Autodesk Fusion 360 part; units mm, degrees
(part 3 of 5)
sketch "Sketch4" plane through (0, 0, 10) normal (0, 0, 1) x (-1, 0, 0)
  arc A0 (-19.4622, 2.96) -> (-19.5078, 2.643) centre (0, 0) ccw
  arc A1 (-20.5849, 1.781) -> (-19.5078, 2.643) centre (-20.4987, 2.7773) ccw
  line L0 (-20.5849, 1.781) -> (-20.5963, 1.782)
  spline S0 degree 5 poles (-20.5963, 1.782) (-20.606, 1.7828) (-20.6255, 1.7842) (-20.6547, 1.7856) (-20.6937, 1.7861) (-20.7426, 1.7846) (-20.7915, 1.7818) (-20.8404, 1.7781) (-20.8894, 1.7739) (-20.9384, 1.7693) (-20.9874, 1.7645) (-21.0364, 1.7592) (-21.0854, 1.7533) (-21.1344, 1.7468) (-21.1835, 1.7395) (-21.2325, 1.7317) (-21.2815, 1.7232) (-21.3306, 1.7143) (-21.3796, 1.705) (-21.4286, 1.6954) (-21.4776, 1.6853) (-21.5266, 1.6749) (-21.5756, 1.6641) (-21.6246, 1.6528) (-21.6736, 1.6411) (-21.7225, 1.629) (-21.7714, 1.6165) (-21.8204, 1.6036) (-21.8693, 1.5904) (-21.9182, 1.5768) (-21.967, 1.5629) (-22.0159, 1.5487) (-22.0647, 1.5341) (-22.1135, 1.5191) (-22.1622, 1.5038) (-22.211, 1.4882) (-22.2597, 1.4723) (-22.3084, 1.456) (-22.3571, 1.4394) (-22.4057, 1.4225) (-22.4543, 1.4053) (-22.5029, 1.3878) (-22.5514, 1.37) (-22.6, 1.3519) (-22.6484, 1.3335) (-22.6969, 1.3148) (-22.7453, 1.2958) (-22.7937, 1.2765) (-22.842, 1.2569) (-22.8903, 1.237) (-22.9386, 1.2169) (-22.9868, 1.1964) (-23.035, 1.1757) (-23.0832, 1.1548) (-23.1313, 1.1335) (-23.1794, 1.112) (-23.2274, 1.0902) (-23.2754, 1.0681) (-23.3233, 1.0457) (-23.3712, 1.0231) (-23.4191, 1.0003) (-23.4669, 0.9772) (-23.5146, 0.9538) (-23.5624, 0.9301) (-23.61, 0.9062) (-23.6577, 0.8821) (-23.7052, 0.8577) (-23.7528, 0.833) (-23.8002, 0.8081) (-23.8477, 0.7829) (-23.895, 0.7575) (-23.9329, 0.737) (-23.9613, 0.7215) (-23.9802, 0.7111) (-23.9896, 0.7059) knots 0 0 0 0 0 0 0.01428571 0.02857143 0.04285714 0.05714286 0.07142857 0.08571429 0.1 0.11428571 0.12857143 0.14285714 0.15714286 0.17142857 0.18571429 0.2 0.21428571 0.22857143 0.24285714 0.25714286 0.27142857 0.28571429 0.3 0.31428571 0.32857143 0.34285714 0.35714286 0.37142857 0.38571429 0.4 0.41428571 0.42857143 0.44285714 0.45714286 0.47142857 0.48571429 0.5 0.51428571 0.52857143 0.54285714 0.55714286 0.57142857 0.58571429 0.6 0.61428571 0.62857143 0.64285714 0.65714286 0.67142857 0.68571429 0.7 0.71428571 0.72857143 0.74285714 0.75714286 0.77142857 0.78571429 0.8 0.81428571 0.82857143 0.84285714 0.85714286 0.87142857 0.88571429 0.9 0.91428571 0.92857143 0.94285714 0.95714286 0.97142857 0.98571429 1 1 1 1 1 1
  arc A2 (-23.9896, 0.7059) -> (-23.9896, -0.7059) centre (0, 0) ccw
  spline S1 degree 5 poles (-23.9896, -0.7059) (-23.9802, -0.7111) (-23.9613, -0.7215) (-23.9329, -0.737) (-23.895, -0.7575) (-23.8477, -0.7829) (-23.8002, -0.8081) (-23.7528, -0.833) (-23.7052, -0.8577) (-23.6577, -0.8821) (-23.61, -0.9062) (-23.5624, -0.9301) (-23.5146, -0.9538) (-23.4669, -0.9772) (-23.4191, -1.0003) (-23.3712, -1.0231) (-23.3233, -1.0457) (-23.2754, -1.0681) (-23.2274, -1.0902) (-23.1794, -1.112) (-23.1313, -1.1335) (-23.0832, -1.1548) (-23.035, -1.1757) (-22.9868, -1.1964) (-22.9386, -1.2169) (-22.8903, -1.237) (-22.842, -1.2569) (-22.7937, -1.2765) (-22.7453, -1.2958) (-22.6969, -1.3148) (-22.6484, -1.3335) (-22.6, -1.3519) (-22.5514, -1.37) (-22.5029, -1.3878) (-22.4543, -1.4053) (-22.4057, -1.4225) (-22.3571, -1.4394) (-22.3084, -1.456) (-22.2597, -1.4723) (-22.211, -1.4882) (-22.1622, -1.5038) (-22.1135, -1.5191) (-22.0647, -1.5341) (-22.0159, -1.5487) (-21.967, -1.5629) (-21.9182, -1.5768) (-21.8693, -1.5904) (-21.8204, -1.6036) (-21.7714, -1.6165) (-21.7225, -1.629) (-21.6736, -1.6411) (-21.6246, -1.6528) (-21.5756, -1.6641) (-21.5266, -1.6749) (-21.4776, -1.6853) (-21.4286, -1.6954) (-21.3796, -1.705) (-21.3306, -1.7143) (-21.2815, -1.7232) (-21.2325, -1.7317) (-21.1835, -1.7395) (-21.1344, -1.7468) (-21.0854, -1.7533) (-21.0364, -1.7592) (-20.9874, -1.7645) (-20.9384, -1.7693) (-20.8894, -1.7739) (-20.8404, -1.7781) (-20.7915, -1.7818) (-20.7426, -1.7846) (-20.6937, -1.7861) (-20.6547, -1.7856) (-20.6255, -1.7842) (-20.606, -1.7828) (-20.5963, -1.782) knots -1 -1 -1 -1 -1 -1 -0.98571429 -0.97142857 -0.95714286 -0.94285714 -0.92857143 -0.91428571 -0.9 -0.88571429 -0.87142857 -0.85714286 -0.84285714 -0.82857143 -0.81428571 -0.8 -0.78571429 -0.77142857 -0.75714286 -0.74285714 -0.72857143 -0.71428571 -0.7 -0.68571429 -0.67142857 -0.65714286 -0.64285714 -0.62857143 -0.61428571 -0.6 -0.58571429 -0.57142857 -0.55714286 -0.54285714 -0.52857143 -0.51428571 -0.5 -0.48571429 -0.47142857 -0.45714286 -0.44285714 -0.42857143 -0.41428571 -0.4 -0.38571429 -0.37142857 -0.35714286 -0.34285714 -0.32857143 -0.31428571 -0.3 -0.28571429 -0.27142857 -0.25714286 -0.24285714 -0.22857143 -0.21428571 -0.2 -0.18571429 -0.17142857 -0.15714286 -0.14285714 -0.12857143 -0.11428571 -0.1 -0.08571429 -0.07142857 -0.05714286 -0.04285714 -0.02857143 -0.01428571 0 0 0 0 0 0
  line L1 (-20.5963, -1.782) -> (-20.5849, -1.781)
  arc A3 (-19.5078, -2.643) -> (-20.5849, -1.781) centre (-20.4987, -2.7773) ccw
  arc A4 (-19.5078, -2.643) -> (-19.4622, -2.96) centre (0, 0) ccw
  arc A5 (-20.2528, -4.0906) -> (-19.4622, -2.96) centre (-20.4508, -3.1104) ccw
  line L2 (-20.2528, -4.0906) -> (-20.264, -4.0929)
  spline S2 degree 5 poles (-20.264, -4.0929) (-20.2736, -4.0948) (-20.2927, -4.0989) (-20.3211, -4.1058) (-20.3587, -4.1164) (-20.4052, -4.1315) (-20.4513, -4.148) (-20.4972, -4.1654) (-20.543, -4.1832) (-20.5887, -4.2013) (-20.6344, -4.2198) (-20.6799, -4.2387) (-20.7253, -4.2581) (-20.7705, -4.2782) (-20.8155, -4.299) (-20.8603, -4.3204) (-20.905, -4.3423) (-20.9495, -4.3646) (-20.9939, -4.3874) (-21.0382, -4.4104) (-21.0824, -4.4339) (-21.1265, -4.4577) (-21.1705, -4.4819) (-21.2143, -4.5065) (-21.258, -4.5315) (-21.3015, -4.5569) (-21.345, -4.5827) (-21.3883, -4.6089) (-21.4315, -4.6353) (-21.4746, -4.6621) (-21.5175, -4.6892) (-21.5604, -4.7167) (-21.6031, -4.7444) (-21.6457, -4.7725) (-21.6882, -4.8009) (-21.7306, -4.8296) (-21.7728, -4.8586) (-21.815, -4.888) (-21.857, -4.9176) (-21.8989, -4.9475) (-21.9407, -4.9777) (-21.9824, -5.0082) (-22.0239, -5.039) (-22.0654, -5.07) (-22.1067, -5.1013) (-22.1479, -5.1329) (-22.189, -5.1648) (-22.23, -5.1969) (-22.2709, -5.2294) (-22.3116, -5.262) (-22.3523, -5.295) (-22.3928, -5.3282) (-22.4332, -5.3616) (-22.4735, -5.3953) (-22.5136, -5.4293) (-22.5537, -5.4635) (-22.5936, -5.4979) (-22.6335, -5.5326) (-22.6732, -5.5675) (-22.7128, -5.6027) (-22.7522, -5.6382) (-22.7916, -5.6738) (-22.8308, -5.7097) (-22.87, -5.7458) (-22.909, -5.7822) (-22.9479, -5.8188) (-22.9866, -5.8556) (-23.0253, -5.8927) (-23.0638, -5.9299) (-23.1022, -5.9674) (-23.1405, -6.0052) (-23.1711, -6.0355) (-23.1939, -6.0584) (-23.2091, -6.0737) (-23.2167, -6.0813) knots 0 0 0 0 0 0 0.01428571 0.02857143 0.04285714 0.05714286 0.07142857 0.08571429 0.1 0.11428571 0.12857143 0.14285714 0.15714286 0.17142857 0.18571429 0.2 0.21428571 0.22857143 0.24285714 0.25714286 0.27142857 0.28571429 0.3 0.31428571 0.32857143 0.34285714 0.35714286 0.37142857 0.38571429 0.4 0.41428571 0.42857143 0.44285714 0.45714286 0.47142857 0.48571429 0.5 0.51428571 0.52857143 0.54285714 0.55714286 0.57142857 0.58571429 0.6 0.61428571 0.62857143 0.64285714 0.65714286 0.67142857 0.68571429 0.7 0.71428571 0.72857143 0.74285714 0.75714286 0.77142857 0.78571429 0.8 0.81428571 0.82857143 0.84285714 0.85714286 0.87142857 0.88571429 0.9 0.91428571 0.92857143 0.94285714 0.95714286 0.97142857 0.98571429 1 1 1 1 1 1
  arc A6 (-23.2167, -6.0813) -> (-22.819, -7.436) centre (0, 0) ccw
  spline S3 degree 5 poles (-22.819, -7.436) (-22.8085, -7.4383) (-22.7874, -7.4429) (-22.7558, -7.4498) (-22.7137, -7.4589) (-22.6611, -7.4699) (-22.6085, -7.4807) (-22.5559, -7.4912) (-22.5034, -7.5015) (-22.4508, -7.5115) (-22.3984, -7.5212) (-22.3459, -7.5307) (-22.2934, -7.54) (-22.241, -7.549) (-22.1886, -7.5577) (-22.1363, -7.5661) (-22.0839, -7.5743) (-22.0316, -7.5823) (-21.9794, -7.5899) (-21.9272, -7.5973) (-21.875, -7.6044) (-21.8228, -7.6113) (-21.7707, -7.6178) (-21.7186, -7.6241) (-21.6666, -7.6301) (-21.6146, -7.6359) (-21.5627, -7.6413) (-21.5108, -7.6465) (-21.4589, -7.6514) (-21.4071, -7.656) (-21.3553, -7.6603) (-21.3036, -7.6643) (-21.252, -7.668) (-21.2004, -7.6714) (-21.1488, -7.6745) (-21.0973, -7.6773) (-21.0459, -7.6798) (-20.9946, -7.682) (-20.9433, -7.6839) (-20.892, -7.6855) (-20.8408, -7.6867) (-20.7897, -7.6877) (-20.7387, -7.6883) (-20.6878, -7.6885) (-20.6369, -7.6884) (-20.5861, -7.688) (-20.5353, -7.6873) (-20.4847, -7.6862) (-20.4341, -7.6847) (-20.3837, -7.6829) (-20.3333, -7.6808) (-20.283, -7.6782) (-20.2328, -7.6752) (-20.1828, -7.6718) (-20.1328, -7.668) (-20.083, -7.6638) (-20.0332, -7.6593) (-19.9835, -7.6544) (-19.934, -7.6491) (-19.8846, -7.6434) (-19.8353, -7.6371) (-19.7862, -7.6303) (-19.7373, -7.6228) (-19.6886, -7.6146) (-19.6401, -7.6058) (-19.5917, -7.5967) (-19.5435, -7.5872) (-19.4953, -7.5775) (-19.4473, -7.5673) (-19.3996, -7.5562) (-19.3523, -7.5438) (-19.315, -7.5324) (-19.2873, -7.5228) (-19.2691, -7.516) (-19.26, -7.5124) knots -1 -1 -1 -1 -1 -1 -0.98571429 -0.97142857 -0.95714286 -0.94285714 -0.92857143 -0.91428571 -0.9 -0.88571429 -0.87142857 -0.85714286 -0.84285714 -0.82857143 -0.81428571 -0.8 -0.78571429 -0.77142857 -0.75714286 -0.74285714 -0.72857143 -0.71428571 -0.7 -0.68571429 -0.67142857 -0.65714286 -0.64285714 -0.62857143 -0.61428571 -0.6 -0.58571429 -0.57142857 -0.55714286 -0.54285714 -0.52857143 -0.51428571 -0.5 -0.48571429 -0.47142857 -0.45714286 -0.44285714 -0.42857143 -0.41428571 -0.4 -0.38571429 -0.37142857 -0.35714286 -0.34285714 -0.32857143 -0.31428571 -0.3 -0.28571429 -0.27142857 -0.25714286 -0.24285714 -0.22857143 -0.21428571 -0.2 -0.18571429 -0.17142857 -0.15714286 -0.14285714 -0.12857143 -0.11428571 -0.1 -0.08571429 -0.07142857 -0.05714286 -0.04285714 -0.02857143 -0.01428571 0 0 0 0 0 0
  line L3 (-19.26, -7.5124) -> (-19.2493, -7.5083)
  arc A7 (-17.9729, -8.0319) -> (-19.2493, -7.5083) centre (-18.8859, -8.4399) ccw
  arc A8 (-17.9729, -8.0319) -> (-17.8399, -8.3233) centre (0, 0) ccw
  arc A9 (-18.28, -9.6308) -> (-17.8399, -8.3233) centre (-18.7461, -8.7461) ccw
  line L4 (-18.28, -9.6308) -> (-18.2901, -9.6361)
  spline S4 degree 5 poles (-18.2901, -9.6361) (-18.2988, -9.6407) (-18.3159, -9.65) (-18.3413, -9.6646) (-18.3743, -9.6853) (-18.4146, -9.713) (-18.4542, -9.7418) (-18.4934, -9.7714) (-18.5323, -9.8014) (-18.5711, -9.8317) (-18.6097, -9.8622) (-18.648, -9.8932) (-18.6861, -9.9246) (-18.7238, -9.9567) (-18.7611, -9.9893) (-18.7981, -10.0224) (-18.8348, -10.056) (-18.8712, -10.09) (-18.9075, -10.1243) (-18.9435, -10.1589) (-18.9793, -10.1939) (-19.0149, -10.2291) (-19.0502, -10.2648) (-19.0853, -10.3007) (-19.1202, -10.337) (-19.1548, -10.3737) (-19.1892, -10.4107) (-19.2234, -10.4479) (-19.2574, -10.4855) (-19.2912, -10.5233) (-19.3248, -10.5615) (-19.3582, -10.5999) (-19.3914, -10.6385) (-19.4243, -10.6775) (-19.4571, -10.7167) (-19.4897, -10.7562) (-19.522, -10.7959) (-19.5542, -10.836) (-19.5862, -10.8762) (-19.618, -10.9167) (-19.6496, -10.9575) (-19.681, -10.9985) (-19.7122, -11.0397) (-19.7432, -11.0812) (-19.774, -11.1229) (-19.8047, -11.1648) (-19.8351, -11.207) (-19.8654, -11.2494) (-19.8955, -11.292) (-19.9254, -11.3348) (-19.9551, -11.3778) (-19.9846, -11.4211) (-20.0139, -11.4646) (-20.0431, -11.5083) (-20.0721, -11.5522) (-20.1009, -11.5963) (-20.1295, -11.6406) (-20.1579, -11.6851) (-20.1862, -11.7298) (-20.2143, -11.7747) (-20.2422, -11.8198) (-20.2699, -11.8651) (-20.2974, -11.9106) (-20.3248, -11.9563) (-20.352, -12.0022) (-20.379, -12.0483) (-20.4058, -12.0945) (-20.4324, -12.1409) (-20.4589, -12.1876) (-20.4852, -12.2344) (-20.5113, -12.2814) (-20.5321, -12.3191) (-20.5476, -12.3475) (-20.5579, -12.3664) (-20.563, -12.3759) knots 0 0 0 0 0 0 0.01428571 0.02857143 0.04285714 0.05714286 0.07142857 0.08571429 0.1 0.11428571 0.12857143 0.14285714 0.15714286 0.17142857 0.18571429 0.2 0.21428571 0.22857143 0.24285714 0.25714286 0.27142857 0.28571429 0.3 0.31428571 0.32857143 0.34285714 0.35714286 0.37142857 0.38571429 0.4 0.41428571 0.42857143 0.44285714 0.45714286 0.47142857 0.48571429 0.5 0.51428571 0.52857143 0.54285714 0.55714286 0.57142857 0.58571429 0.6 0.61428571 0.62857143 0.64285714 0.65714286 0.67142857 0.68571429 0.7 0.71428571 0.72857143 0.74285714 0.75714286 0.77142857 0.78571429 0.8 0.81428571 0.82857143 0.84285714 0.85714286 0.87142857 0.88571429 0.9 0.91428571 0.92857143 0.94285714 0.95714286 0.97142857 0.98571429 1 1 1 1 1 1
  arc A10 (-20.563, -12.3759) -> (-19.7997, -13.5636) centre (0, 0) ccw
  spline S5 degree 5 poles (-19.7997, -13.5636) (-19.7889, -13.5629) (-19.7674, -13.5614) (-19.7352, -13.5591) (-19.6922, -13.5559) (-19.6386, -13.5517) (-19.5851, -13.5472) (-19.5317, -13.5425) (-19.4784, -13.5375) (-19.4252, -13.5323) (-19.3721, -13.5269) (-19.3191, -13.5212) (-19.2661, -13.5153) (-19.2133, -13.5092) (-19.1606, -13.5028) (-19.108, -13.4962) (-19.0554, -13.4893) (-19.003, -13.4821) (-18.9507, -13.4748) (-18.8985, -13.4671) (-18.8465, -13.4593) (-18.7945, -13.4511) (-18.7426, -13.4428) (-18.6909, -13.4341) (-18.6393, -13.4252) (-18.5878, -13.4161) (-18.5364, -13.4067) (-18.4851, -13.397) (-18.434, -13.3871) (-18.383, -13.3769) (-18.3321, -13.3665) (-18.2814, -13.3558) (-18.2308, -13.3448) (-18.1803, -13.3335) (-18.13, -13.322) (-18.0798, -13.3102) (-18.0298, -13.2981) (-17.9798, -13.2857) (-17.9301, -13.2731) (-17.8805, -13.2601) (-17.831, -13.2469) (-17.7817, -13.2334) (-17.7326, -13.2196) (-17.6836, -13.2055) (-17.6349, -13.1911) (-17.5862, -13.1764) (-17.5378, -13.1613) (-17.4895, -13.146) (-17.4414, -13.1304) (-17.3934, -13.1145) (-17.3457, -13.0982) (-17.2982, -13.0815) (-17.2509, -13.0646) (-17.2038, -13.0472) (-17.157, -13.0295) (-17.1103, -13.0114) (-17.0638, -12.993) (-17.0176, -12.9744) (-16.9715, -12.9553) (-16.9257, -12.9359) (-16.8802, -12.916) (-16.835, -12.8956) (-16.7902, -12.8746) (-16.7458, -12.8531) (-16.7017, -12.831) (-16.6579, -12.8086) (-16.6142, -12.7859) (-16.5708, -12.763) (-16.5276, -12.7397) (-16.4849, -12.7156) (-16.4431, -12.6904) (-16.4105, -12.669) (-16.3866, -12.652) (-16.371, -12.6403) (-16.3633, -12.6343) knots -1 -1 -1 -1 -1 -1 -0.98571429 -0.97142857 -0.95714286 -0.94285714 -0.92857143 -0.91428571 -0.9 -0.88571429 -0.87142857 -0.85714286 -0.84285714 -0.82857143 -0.81428571 -0.8 -0.78571429 -0.77142857 -0.75714286 -0.74285714 -0.72857143 -0.71428571 -0.7 -0.68571429 -0.67142857 -0.65714286 -0.64285714 -0.62857143 -0.61428571 -0.6 -0.58571429 -0.57142857 -0.55714286 -0.54285714 -0.52857143 -0.51428571 -0.5 -0.48571429 -0.47142857 -0.45714286 -0.44285714 -0.42857143 -0.41428571 -0.4 -0.38571429 -0.37142857 -0.35714286 -0.34285714 -0.32857143 -0.31428571 -0.3 -0.28571429 -0.27142857 -0.25714286 -0.24285714 -0.22857143 -0.21428571 -0.2 -0.18571429 -0.17142857 -0.15714286 -0.14285714 -0.12857143 -0.11428571 -0.1 -0.08571429 -0.07142857 -0.05714286 -0.04285714 -0.02857143 -0.01428571 0 0 0 0 0 0
  line L5 (-16.3633, -12.6343) -> (-16.3543, -12.6273)
  arc A11 (-14.9821, -12.7701) -> (-16.3543, -12.6273) centre (-15.7431, -13.4188) ccw
  arc A12 (-14.9821, -12.7701) -> (-14.7723, -13.0122) centre (0, 0) ccw
  arc A13 (-14.8262, -14.3907) -> (-14.7723, -13.0122) centre (-15.5227, -13.6732) ccw
  line L6 (-14.8262, -14.3907) -> (-14.8344, -14.3987)
  spline S6 degree 5 poles (-14.8344, -14.3987) (-14.8414, -14.4055) (-14.8553, -14.4193) (-14.8755, -14.4405) (-14.9013, -14.4697) (-14.9322, -14.5075) (-14.9621, -14.5463) (-14.9914, -14.5858) (-15.0202, -14.6255) (-15.0489, -14.6655) (-15.0773, -14.7057) (-15.1054, -14.7462) (-15.1331, -14.7871) (-15.1602, -14.8284) (-15.1869, -14.8702) (-15.213, -14.9125) (-15.2388, -14.955) (-15.2641, -14.9979) (-15.2892, -15.041) (-15.314, -15.0844) (-15.3385, -15.128) (-15.3628, -15.1719) (-15.3866, -15.216) (-15.4102, -15.2604) (-15.4334, -15.3051) (-15.4563, -15.35) (-15.4789, -15.3952) (-15.5012, -15.4406) (-15.5233, -15.4862) (-15.545, -15.532) (-15.5665, -15.5781) (-15.5877, -15.6243) (-15.6087, -15.6708) (-15.6293, -15.7174) (-15.6497, -15.7643) (-15.6698, -15.8114) (-15.6897, -15.8586) (-15.7093, -15.9061) (-15.7286, -15.9537) (-15.7477, -16.0015) (-15.7665, -16.0495) (-15.7851, -16.0977) (-15.8034, -16.1461) (-15.8215, -16.1946) (-15.8394, -16.2433) (-15.8569, -16.2922) (-15.8743, -16.3412) (-15.8914, -16.3904) (-15.9082, -16.4398) (-15.9249, -16.4893) (-15.9412, -16.5389) (-15.9574, -16.5888) (-15.9733, -16.6388) (-15.989, -16.6889) (-16.0044, -16.7392) (-16.0196, -16.7896) (-16.0346, -16.8402) (-16.0493, -16.8909) (-16.0638, -16.9418) (-16.0781, -16.9928) (-16.0922, -17.0439) (-16.106, -17.0952) (-16.1196, -17.1466) (-16.133, -17.1981) (-16.1462, -17.2498) (-16.1591, -17.3016) (-16.1718, -17.3536) (-16.1843, -17.4056) (-16.1966, -17.4578) (-16.2086, -17.5101) (-16.2204, -17.5626) (-16.2297, -17.6046) (-16.2366, -17.6362) (-16.2411, -17.6573) (-16.2434, -17.6679) knots 0 0 0 0 0 0 0.01428571 0.02857143 0.04285714 0.05714286 0.07142857 0.08571429 0.1 0.11428571 0.12857143 0.14285714 0.15714286 0.17142857 0.18571429 0.2 0.21428571 0.22857143 0.24285714 0.25714286 0.27142857 0.28571429 0.3 0.31428571 0.32857143 0.34285714 0.35714286 0.37142857 0.38571429 0.4 0.41428571 0.42857143 0.44285714 0.45714286 0.47142857 0.48571429 0.5 0.51428571 0.52857143 0.54285714 0.55714286 0.57142857 0.58571429 0.6 0.61428571 0.62857143 0.64285714 0.65714286 0.67142857 0.68571429 0.7 0.71428571 0.72857143 0.74285714 0.75714286 0.77142857 0.78571429 0.8 0.81428571 0.82857143 0.84285714 0.85714286 0.87142857 0.88571429 0.9 0.91428571 0.92857143 0.94285714 0.95714286 0.97142857 0.98571429 1 1 1 1 1 1
  arc A14 (-16.2434, -17.6679) -> (-15.1764, -18.5924) centre (0, 0) ccw
  spline S7 degree 5 poles (-15.1764, -18.5924) (-15.1662, -18.5887) (-15.146, -18.5812) (-15.1157, -18.5699) (-15.0754, -18.5547) (-15.0252, -18.5356) (-14.9751, -18.5162) (-14.9252, -18.4966) (-14.8754, -18.4769) (-14.8258, -18.4569) (-14.7764, -18.4367) (-14.7271, -18.4163) (-14.678, -18.3958) (-14.6291, -18.375) (-14.5803, -18.354) (-14.5316, -18.3328) (-14.4832, -18.3114) (-14.4349, -18.2898) (-14.3868, -18.268) (-14.3389, -18.246) (-14.2911, -18.2237) (-14.2436, -18.2013) (-14.1962, -18.1787) (-14.149, -18.1558) (-14.1019, -18.1327) (-14.0551, -18.1094) (-14.0084, -18.0859) (-13.962, -18.0622) (-13.9157, -18.0383) (-13.8697, -18.0142) (-13.8238, -17.9898) (-13.7781, -17.9652) (-13.7327, -17.9404) (-13.6874, -17.9154) (-13.6424, -17.8901) (-13.5975, -17.8647) (-13.5529, -17.839) (-13.5085, -17.8131) (-13.4643, -17.7869) (-13.4204, -17.7605) (-13.3767, -17.7339) (-13.3332, -17.7071) (-13.2899, -17.68) (-13.2469, -17.6526) (-13.2042, -17.6251) (-13.1617, -17.5972) (-13.1194, -17.5692) (-13.0774, -17.5409) (-13.0356, -17.5123) (-12.9941, -17.4835) (-12.9529, -17.4545) (-12.912, -17.4251) (-12.8714, -17.3955) (-12.8311, -17.3656) (-12.7912, -17.3354) (-12.7515, -17.3049) (-12.7121, -17.2742) (-12.6729, -17.2432) (-12.6341, -17.212) (-12.5956, -17.1804) (-12.5576, -17.1485) (-12.52, -17.1162) (-12.4829, -17.0835) (-12.4464, -17.0503) (-12.4103, -17.0167) (-12.3745, -16.9828) (-12.339, -16.9488) (-12.3038, -16.9145) (-12.2689, -16.88) (-12.2348, -16.8449) (-12.2017, -16.8089) (-12.1765, -16.7791) (-12.1584, -16.7561) (-12.1467, -16.7405) (-12.141, -16.7326) knots -1 -1 -1 -1 -1 -1 -0.98571429 -0.97142857 -0.95714286 -0.94285714 -0.92857143 -0.91428571 -0.9 -0.88571429 -0.87142857 -0.85714286 -0.84285714 -0.82857143 -0.81428571 -0.8 -0.78571429 -0.77142857 -0.75714286 -0.74285714 -0.72857143 -0.71428571 -0.7 -0.68571429 -0.67142857 -0.65714286 -0.64285714 -0.62857143 -0.61428571 -0.6 -0.58571429 -0.57142857 -0.55714286 -0.54285714 -0.52857143 -0.51428571 -0.5 -0.48571429 -0.47142857 -0.45714286 -0.44285714 -0.42857143 -0.41428571 -0.4 -0.38571429 -0.37142857 -0.35714286 -0.34285714 -0.32857143 -0.31428571 -0.3 -0.28571429 -0.27142857 -0.25714286 -0.24285714 -0.22857143 -0.21428571 -0.2 -0.18571429 -0.17142857 -0.15714286 -0.14285714 -0.12857143 -0.11428571 -0.1 -0.08571429 -0.07142857 -0.05714286 -0.04285714 -0.02857143 -0.01428571 0 0 0 0 0 0
  line L7 (-12.141, -16.7326) -> (-12.1343, -16.7233)
  arc A15 (-10.7774, -16.4738) -> (-12.1343, -16.7233) centre (-11.3249, -17.3106) ccw
  arc A16 (-10.7774, -16.4738) -> (-10.508, -16.6469) centre (0, 0) ccw
  arc A17 (-10.1713, -17.9848) -> (-10.508, -16.6469) centre (-11.0418, -17.4926) ccw
  line L8 (-10.1713, -17.9848) -> (-10.1769, -17.9948)
  spline S8 degree 5 poles (-10.1769, -17.9948) (-10.1818, -18.0033) (-10.1912, -18.0204) (-10.2046, -18.0464) (-10.2212, -18.0817) (-10.2401, -18.1268) (-10.2579, -18.1724) (-10.2748, -18.2185) (-10.2913, -18.2648) (-10.3076, -18.3112) (-10.3235, -18.3578) (-10.3391, -18.4046) (-10.3541, -18.4516) (-10.3685, -18.4989) (-10.3823, -18.5465) (-10.3955, -18.5944) (-10.4082, -18.6425) (-10.4204, -18.6908) (-10.4324, -18.7393) (-10.4439, -18.7879) (-10.4552, -18.8366) (-10.466, -18.8855) (-10.4765, -18.9346) (-10.4866, -18.9838) (-10.4963, -19.0332) (-10.5056, -19.0828) (-10.5146, -19.1325) (-10.5232, -19.1823) (-10.5315, -19.2323) (-10.5395, -19.2824) (-10.5471, -19.3326) (-10.5544, -19.383) (-10.5614, -19.4335) (-10.5681, -19.4841) (-10.5745, -19.5348) (-10.5805, -19.5856) (-10.5863, -19.6365) (-10.5917, -19.6876) (-10.5968, -19.7387) (-10.6017, -19.79) (-10.6062, -19.8414) (-10.6105, -19.8928) (-10.6144, -19.9444) (-10.6181, -19.996) (-10.6215, -20.0478) (-10.6246, -20.0996) (-10.6274, -20.1516) (-10.63, -20.2036) (-10.6322, -20.2557) (-10.6342, -20.3079) (-10.636, -20.3602) (-10.6374, -20.4125) (-10.6386, -20.465) (-10.6395, -20.5175) (-10.6401, -20.5701) (-10.6405, -20.6228) (-10.6406, -20.6755) (-10.6405, -20.7283) (-10.6401, -20.7812) (-10.6394, -20.8342) (-10.6385, -20.8872) (-10.6373, -20.9403) (-10.6359, -20.9935) (-10.6342, -21.0467) (-10.6323, -21.1) (-10.6301, -21.1533) (-10.6277, -21.2068) (-10.625, -21.2602) (-10.622, -21.3138) (-10.6189, -21.3673) (-10.6154, -21.421) (-10.6125, -21.464) (-10.6102, -21.4962) (-10.6086, -21.5177) (-10.6078, -21.5285) knots 0 0 0 0 0 0 0.01428571 0.02857143 0.04285714 0.05714286 0.07142857 0.08571429 0.1 0.11428571 0.12857143 0.14285714 0.15714286 0.17142857 0.18571429 0.2 0.21428571 0.22857143 0.24285714 0.25714286 0.27142857 0.28571429 0.3 0.31428571 0.32857143 0.34285714 0.35714286 0.37142857 0.38571429 0.4 0.41428571 0.42857143 0.44285714 0.45714286 0.47142857 0.48571429 0.5 0.51428571 0.52857143 0.54285714 0.55714286 0.57142857 0.58571429 0.6 0.61428571 0.62857143 0.64285714 0.65714286 0.67142857 0.68571429 0.7 0.71428571 0.72857143 0.74285714 0.75714286 0.77142857 0.78571429 0.8 0.81428571 0.82857143 0.84285714 0.85714286 0.87142857 0.88571429 0.9 0.91428571 0.92857143 0.94285714 0.95714286 0.97142857 0.98571429 1 1 1 1 1 1
  arc A18 (-10.6078, -21.5285) -> (-9.3235, -22.115) centre (0, 0) ccw
  spline S9 degree 5 poles (-9.3235, -22.115) (-9.3149, -22.1085) (-9.2976, -22.0957) (-9.2717, -22.0763) (-9.2373, -22.0504) (-9.1945, -22.0178) (-9.1519, -21.9851) (-9.1095, -21.9523) (-9.0674, -21.9193) (-9.0254, -21.8862) (-8.9836, -21.8529) (-8.9421, -21.8195) (-8.9008, -21.7859) (-8.8596, -21.7522) (-8.8187, -21.7183) (-8.7781, -21.6842) (-8.7376, -21.6501) (-8.6974, -21.6157) (-8.6574, -21.5812) (-8.6176, -21.5466) (-8.578, -21.5118) (-8.5387, -21.4769) (-8.4996, -21.4418) (-8.4607, -21.4066) (-8.4221, -21.3712) (-8.3837, -21.3357) (-8.3456, -21.3) (-8.3077, -21.2641) (-8.2701, -21.2281) (-8.2327, -21.192) (-8.1955, -21.1557) (-8.1586, -21.1192) (-8.122, -21.0826) (-8.0856, -21.0459) (-8.0495, -21.009) (-8.0137, -20.9719) (-7.9781, -20.9347) (-7.9428, -20.8973) (-7.9078, -20.8598) (-7.873, -20.8221) (-7.8386, -20.7842) (-7.8044, -20.7462) (-7.7706, -20.708) (-7.737, -20.6697) (-7.7038, -20.6312) (-7.6708, -20.5925) (-7.6382, -20.5537) (-7.6058, -20.5147) (-7.5738, -20.4755) (-7.5421, -20.4362) (-7.5107, -20.3967) (-7.4798, -20.357) (-7.4491, -20.3171) (-7.4189, -20.2771) (-7.3891, -20.2368) (-7.3596, -20.1964) (-7.3304, -20.1559) (-7.3016, -20.1151) (-7.2732, -20.0742) (-7.2451, -20.0331) (-7.2176, -19.9918) (-7.1906, -19.9502) (-7.1643, -19.9083) (-7.1386, -19.8662) (-7.1134, -19.8238) (-7.0887, -19.7812) (-7.0642, -19.7385) (-7.04, -19.6958) (-7.0163, -19.6528) (-6.9934, -19.6095) (-6.9718, -19.5657) (-6.956, -19.53) (-6.9451, -19.5028) (-6.9383, -19.4845) (-6.9351, -19.4753) knots -1 -1 -1 -1 -1 -1 -0.98571429 -0.97142857 -0.95714286 -0.94285714 -0.92857143 -0.91428571 -0.9 -0.88571429 -0.87142857 -0.85714286 -0.84285714 -0.82857143 -0.81428571 -0.8 -0.78571429 -0.77142857 -0.75714286 -0.74285714 -0.72857143 -0.71428571 -0.7 -0.68571429 -0.67142857 -0.65714286 -0.64285714 -0.62857143 -0.61428571 -0.6 -0.58571429 -0.57142857 -0.55714286 -0.54285714 -0.52857143 -0.51428571 -0.5 -0.48571429 -0.47142857 -0.45714286 -0.44285714 -0.42857143 -0.41428571 -0.4 -0.38571429 -0.37142857 -0.35714286 -0.34285714 -0.32857143 -0.31428571 -0.3 -0.28571429 -0.27142857 -0.25714286 -0.24285714 -0.22857143 -0.21428571 -0.2 -0.18571429 -0.17142857 -0.15714286 -0.14285714 -0.12857143 -0.11428571 -0.1 -0.08571429 -0.07142857 -0.05714286 -0.04285714 -0.02857143 -0.01428571 0 0 0 0 0 0
  line L9 (-6.9351, -19.4753) -> (-6.9312, -19.4645)
  arc A19 (-5.6997, -18.8428) -> (-6.9312, -19.4645) centre (-5.9892, -19.8) ccw
  arc A20 (-5.6997, -18.8428) -> (-5.3924, -18.9331) centre (0, 0) ccw
  arc A21 (-4.6924, -20.1219) -> (-5.3924, -18.9331) centre (-5.6663, -19.8948) ccw
  line L10 (-4.6924, -20.1219) -> (-4.695, -20.1331)
  spline S10 degree 5 poles (-4.695, -20.1331) (-4.6972, -20.1426) (-4.7014, -20.1616) (-4.7069, -20.1904) (-4.7129, -20.2289) (-4.7185, -20.2775) (-4.7226, -20.3263) (-4.7259, -20.3753) (-4.7287, -20.4243) (-4.7312, -20.4734) (-4.7334, -20.5226) (-4.7351, -20.5719) (-4.7363, -20.6213) (-4.7367, -20.6707) (-4.7365, -20.7203) (-4.7357, -20.7699) (-4.7344, -20.8197) (-4.7325, -20.8695) (-4.7303, -20.9193) (-4.7277, -20.9692) (-4.7248, -21.0192) (-4.7214, -21.0691) (-4.7177, -21.1192) (-4.7135, -21.1693) (-4.7089, -21.2194) (-4.7038, -21.2696) (-4.6984, -21.3198) (-4.6927, -21.3701) (-4.6865, -21.4203) (-4.6801, -21.4707) (-4.6732, -21.521) (-4.6661, -21.5714) (-4.6586, -21.6218) (-4.6507, -21.6722) (-4.6425, -21.7226) (-4.634, -21.7731) (-4.6252, -21.8236) (-4.616, -21.8741) (-4.6065, -21.9247) (-4.5967, -21.9752) (-4.5866, -22.0258) (-4.5762, -22.0763) (-4.5655, -22.1269) (-4.5545, -22.1775) (-4.5431, -22.2281) (-4.5315, -22.2788) (-4.5196, -22.3294) (-4.5074, -22.38) (-4.4949, -22.4307) (-4.4821, -22.4813) (-4.469, -22.5319) (-4.4556, -22.5826) (-4.442, -22.6332) (-4.4281, -22.6839) (-4.4139, -22.7345) (-4.3994, -22.7852) (-4.3847, -22.8358) (-4.3696, -22.8865) (-4.3544, -22.9371) (-4.3388, -22.9877) (-4.323, -23.0383) (-4.3069, -23.089) (-4.2905, -23.1396) (-4.2739, -23.1902) (-4.2571, -23.2408) (-4.2399, -23.2913) (-4.2225, -23.3419) (-4.2049, -23.3924) (-4.187, -23.443) (-4.1688, -23.4935) (-4.1504, -23.544) (-4.1355, -23.5844) (-4.1242, -23.6147) (-4.1166, -23.6349) (-4.1128, -23.645) knots 0 0 0 0 0 0 0.01428571 0.02857143 0.04285714 0.05714286 0.07142857 0.08571429 0.1 0.11428571 0.12857143 0.14285714 0.15714286 0.17142857 0.18571429 0.2 0.21428571 0.22857143 0.24285714 0.25714286 0.27142857 0.28571429 0.3 0.31428571 0.32857143 0.34285714 0.35714286 0.37142857 0.38571429 0.4 0.41428571 0.42857143 0.44285714 0.45714286 0.47142857 0.48571429 0.5 0.51428571 0.52857143 0.54285714 0.55714286 0.57142857 0.58571429 0.6 0.61428571 0.62857143 0.64285714 0.65714286 0.67142857 0.68571429 0.7 0.71428571 0.72857143 0.74285714 0.75714286 0.77142857 0.78571429 0.8 0.81428571 0.82857143 0.84285714 0.85714286 0.87142857 0.88571429 0.9 0.91428571 0.92857143 0.94285714 0.95714286 0.97142857 0.98571429 1 1 1 1 1 1
  arc A22 (-4.1128, -23.645) -> (-2.7153, -23.8459) centre (0, 0) ccw
  spline S11 degree 5 poles (-2.7153, -23.8459) (-2.7088, -23.8373) (-2.6959, -23.8201) (-2.6765, -23.7942) (-2.6508, -23.7596) (-2.6189, -23.7163) (-2.5873, -23.673) (-2.5558, -23.6295) (-2.5247, -23.586) (-2.4937, -23.5424) (-2.4631, -23.4987) (-2.4326, -23.4549) (-2.4024, -23.411) (-2.3725, -23.3671) (-2.3428, -23.3231) (-2.3133, -23.2789) (-2.2841, -23.2347) (-2.2552, -23.1905) (-2.2265, -23.1461) (-2.1981, -23.1017) (-2.17, -23.0572) (-2.1421, -23.0126) (-2.1145, -22.9679) (-2.0871, -22.9231) (-2.06, -22.8783) (-2.0332, -22.8334) (-2.0067, -22.7884) (-1.9804, -22.7433) (-1.9544, -22.6982) (-1.9287, -22.653) (-1.9033, -22.6077) (-1.8782, -22.5623) (-1.8533, -22.5169) (-1.8288, -22.4714) (-1.8045, -22.4258) (-1.7806, -22.3801) (-1.757, -22.3344) (-1.7336, -22.2886) (-1.7106, -22.2427) (-1.6879, -22.1967) (-1.6655, -22.1507) (-1.6434, -22.1046) (-1.6217, -22.0584) (-1.6003, -22.0122) (-1.5792, -21.9659) (-1.5585, -21.9195) (-1.5381, -21.873) (-1.5181, -21.8265) (-1.4984, -21.7799) (-1.479, -21.7332) (-1.4601, -21.6865) (-1.4415, -21.6397) (-1.4234, -21.5928) (-1.4057, -21.5459) (-1.3884, -21.4989) (-1.3715, -21.4518) (-1.3549, -21.4046) (-1.3388, -21.3574) (-1.323, -21.3102) (-1.3077, -21.2628) (-1.2929, -21.2154) (-1.2787, -21.1679) (-1.2653, -21.1203) (-1.2525, -21.0726) (-1.2403, -21.0249) (-1.2285, -20.9771) (-1.2171, -20.9292) (-1.2059, -20.8813) (-1.1953, -20.8334) (-1.1855, -20.7854) (-1.1771, -20.7373) (-1.172, -20.6986) (-1.1692, -20.6695) (-1.1679, -20.65) (-1.1673, -20.6403) knots -1 -1 -1 -1 -1 -1 -0.98571429 -0.97142857 -0.95714286 -0.94285714 -0.92857143 -0.91428571 -0.9 -0.88571429 -0.87142857 -0.85714286 -0.84285714 -0.82857143 -0.81428571 -0.8 -0.78571429 -0.77142857 -0.75714286 -0.74285714 -0.72857143 -0.71428571 -0.7 -0.68571429 -0.67142857 -0.65714286 -0.64285714 -0.62857143 -0.61428571 -0.6 -0.58571429 -0.57142857 -0.55714286 -0.54285714 -0.52857143 -0.51428571 -0.5 -0.48571429 -0.47142857 -0.45714286 -0.44285714 -0.42857143 -0.41428571 -0.4 -0.38571429 -0.37142857 -0.35714286 -0.34285714 -0.32857143 -0.31428571 -0.3 -0.28571429 -0.27142857 -0.25714286 -0.24285714 -0.22857143 -0.21428571 -0.2 -0.18571429 -0.17142857 -0.15714286 -0.14285714 -0.12857143 -0.11428571 -0.1 -0.08571429 -0.07142857 -0.05714286 -0.04285714 -0.02857143 -0.01428571 0 0 0 0 0 0
  line L11 (-1.1673, -20.6403) -> (-1.1667, -20.6289)
  arc A23 (-0.1601, -19.6853) -> (-1.1667, -20.6289) centre (-0.1683, -20.6853) ccw
  arc A24 (-0.1601, -19.6853) -> (0.1601, -19.6853) centre (0, 0) ccw
  arc A25 (1.1667, -20.6289) -> (0.1601, -19.6853) centre (0.1683, -20.6853) ccw
  line L12 (1.1667, -20.6289) -> (1.1673, -20.6403)
  spline S12 degree 5 poles (1.1673, -20.6403) (1.1679, -20.65) (1.1692, -20.6695) (1.172, -20.6986) (1.1771, -20.7373) (1.1855, -20.7854) (1.1953, -20.8334) (1.2059, -20.8813) (1.2171, -20.9292) (1.2285, -20.9771) (1.2403, -21.0249) (1.2525, -21.0726) (1.2653, -21.1203) (1.2787, -21.1679) (1.2929, -21.2154) (1.3077, -21.2628) (1.323, -21.3102) (1.3388, -21.3574) (1.3549, -21.4046) (1.3715, -21.4518) (1.3884, -21.4989) (1.4057, -21.5459) (1.4234, -21.5928) (1.4415, -21.6397) (1.4601, -21.6865) (1.479, -21.7332) (1.4984, -21.7799) (1.5181, -21.8265) (1.5381, -21.873) (1.5585, -21.9195) (1.5792, -21.9659) (1.6003, -22.0122) (1.6217, -22.0584) (1.6434, -22.1046) (1.6655, -22.1507) (1.6879, -22.1967) (1.7106, -22.2427) (1.7336, -22.2886) (1.757, -22.3344) (1.7806, -22.3801) (1.8045, -22.4258) (1.8288, -22.4714) (1.8533, -22.5169) (1.8782, -22.5623) (1.9033, -22.6077) (1.9287, -22.653) (1.9544, -22.6982) (1.9804, -22.7433) (2.0067, -22.7884) (2.0332, -22.8334) (2.06, -22.8783) (2.0871, -22.9231) (2.1145, -22.9679) (2.1421, -23.0126) (2.17, -23.0572) (2.1981, -23.1017) (2.2265, -23.1461) (2.2552, -23.1905) (2.2841, -23.2347) (2.3133, -23.2789) (2.3428, -23.3231) (2.3725, -23.3671) (2.4024, -23.411) (2.4326, -23.4549) (2.4631, -23.4987) (2.4937, -23.5424) (2.5247, -23.586) (2.5558, -23.6295) (2.5873, -23.673) (2.6189, -23.7163) (2.6508, -23.7596) (2.6765, -23.7942) (2.6959, -23.8201) (2.7088, -23.8373) (2.7153, -23.8459) knots 0 0 0 0 0 0 0.01428571 0.02857143 0.04285714 0.05714286 0.07142857 0.08571429 0.1 0.11428571 0.12857143 0.14285714 0.15714286 0.17142857 0.18571429 0.2 0.21428571 0.22857143 0.24285714 0.25714286 0.27142857 0.28571429 0.3 0.31428571 0.32857143 0.34285714 0.35714286 0.37142857 0.38571429 0.4 0.41428571 0.42857143 0.44285714 0.45714286 0.47142857 0.48571429 0.5 0.51428571 0.52857143 0.54285714 0.55714286 0.57142857 0.58571429 0.6 0.61428571 0.62857143 0.64285714 0.65714286 0.67142857 0.68571429 0.7 0.71428571 0.72857143 0.74285714 0.75714286 0.77142857 0.78571429 0.8 0.81428571 0.82857143 0.84285714 0.85714286 0.87142857 0.88571429 0.9 0.91428571 0.92857143 0.94285714 0.95714286 0.97142857 0.98571429 1 1 1 1 1 1
  arc A26 (2.7153, -23.8459) -> (4.1128, -23.645) centre (0, 0) ccw
  spline S13 degree 5 poles (4.1128, -23.645) (4.1166, -23.6349) (4.1242, -23.6147) (4.1355, -23.5844) (4.1504, -23.544) (4.1688, -23.4935) (4.187, -23.443) (4.2049, -23.3924) (4.2225, -23.3419) (4.2399, -23.2913) (4.2571, -23.2408) (4.2739, -23.1902) (4.2905, -23.1396) (4.3069, -23.089) (4.323, -23.0383) (4.3388, -22.9877) (4.3544, -22.9371) (4.3696, -22.8865) (4.3847, -22.8358) (4.3994, -22.7852) (4.4139, -22.7345) (4.4281, -22.6839) (4.442, -22.6332) (4.4556, -22.5826) (4.469, -22.5319) (4.4821, -22.4813) (4.4949, -22.4307) (4.5074, -22.38) (4.5196, -22.3294) (4.5315, -22.2788) (4.5431, -22.2281) (4.5545, -22.1775) (4.5655, -22.1269) (4.5762, -22.0763) (4.5866, -22.0258) (4.5967, -21.9752) (4.6065, -21.9247) (4.616, -21.8741) (4.6252, -21.8236) (4.634, -21.7731) (4.6425, -21.7226) (4.6507, -21.6722) (4.6586, -21.6218) (4.6661, -21.5714) (4.6732, -21.521) (4.6801, -21.4707) (4.6865, -21.4203) (4.6927, -21.3701) (4.6984, -21.3198) (4.7038, -21.2696) (4.7089, -21.2194) (4.7135, -21.1693) (4.7177, -21.1192) (4.7214, -21.0691) (4.7248, -21.0192) (4.7277, -20.9692) (4.7303, -20.9193) (4.7325, -20.8695) (4.7344, -20.8197) (4.7357, -20.7699) (4.7365, -20.7203) (4.7367, -20.6707) (4.7363, -20.6213) (4.7351, -20.5719) (4.7334, -20.5226) (4.7312, -20.4734) (4.7287, -20.4243) (4.7259, -20.3753) (4.7226, -20.3263) (4.7185, -20.2775) (4.7129, -20.2289) (4.7069, -20.1904) (4.7014, -20.1616) (4.6972, -20.1426) (4.695, -20.1331) knots -1 -1 -1 -1 -1 -1 -0.98571429 -0.97142857 -0.95714286 -0.94285714 -0.92857143 -0.91428571 -0.9 -0.88571429 -0.87142857 -0.85714286 -0.84285714 -0.82857143 -0.81428571 -0.8 -0.78571429 -0.77142857 -0.75714286 -0.74285714 -0.72857143 -0.71428571 -0.7 -0.68571429 -0.67142857 -0.65714286 -0.64285714 -0.62857143 -0.61428571 -0.6 -0.58571429 -0.57142857 -0.55714286 -0.54285714 -0.52857143 -0.51428571 -0.5 -0.48571429 -0.47142857 -0.45714286 -0.44285714 -0.42857143 -0.41428571 -0.4 -0.38571429 -0.37142857 -0.35714286 -0.34285714 -0.32857143 -0.31428571 -0.3 -0.28571429 -0.27142857 -0.25714286 -0.24285714 -0.22857143 -0.21428571 -0.2 -0.18571429 -0.17142857 -0.15714286 -0.14285714 -0.12857143 -0.11428571 -0.1 -0.08571429 -0.07142857 -0.05714286 -0.04285714 -0.02857143 -0.01428571 0 0 0 0 0 0
  line L13 (4.695, -20.1331) -> (4.6924, -20.1219)
  arc A27 (5.3924, -18.9331) -> (4.6924, -20.1219) centre (5.6663, -19.8948) ccw
  arc A28 (5.3924, -18.9331) -> (5.6997, -18.8428) centre (0, 0) ccw
  arc A29 (6.9312, -19.4645) -> (5.6997, -18.8428) centre (5.9892, -19.8) ccw
  line L14 (6.9312, -19.4645) -> (6.9351, -19.4753)
  spline S14 degree 5 poles (6.9351, -19.4753) (6.9383, -19.4845) (6.9451, -19.5028) (6.956, -19.53) (6.9718, -19.5657) (6.9934, -19.6095) (7.0163, -19.6528) (7.04, -19.6958) (7.0642, -19.7385) (7.0887, -19.7812) (7.1134, -19.8238) (7.1386, -19.8662) (7.1643, -19.9083) (7.1906, -19.9502) (7.2176, -19.9918) (7.2451, -20.0331) (7.2732, -20.0742) (7.3016, -20.1151) (7.3304, -20.1559) (7.3596, -20.1964) (7.3891, -20.2368) (7.4189, -20.2771) (7.4491, -20.3171) (7.4798, -20.357) (7.5107, -20.3967) (7.5421, -20.4362) (7.5738, -20.4755) (7.6058, -20.5147) (7.6382, -20.5537) (7.6708, -20.5925) (7.7038, -20.6312) (7.737, -20.6697) (7.7706, -20.708) (7.8044, -20.7462) (7.8386, -20.7842) (7.873, -20.8221) (7.9078, -20.8598) (7.9428, -20.8973) (7.9781, -20.9347) (8.0137, -20.9719) (8.0495, -21.009) (8.0856, -21.0459) (8.122, -21.0826) (8.1586, -21.1192) (8.1955, -21.1557) (8.2327, -21.192) (8.2701, -21.2281) (8.3077, -21.2641) (8.3456, -21.3) (8.3837, -21.3357) (8.4221, -21.3712) (8.4607, -21.4066) (8.4996, -21.4418) (8.5387, -21.4769) (8.578, -21.5118) (8.6176, -21.5466) (8.6574, -21.5812) (8.6974, -21.6157) (8.7376, -21.6501) (8.7781, -21.6842) (8.8187, -21.7183) (8.8596, -21.7522) (8.9008, -21.7859) (8.9421, -21.8195) (8.9836, -21.8529) (9.0254, -21.8862) (9.0674, -21.9193) (9.1095, -21.9523) (9.1519, -21.9851) (9.1945, -22.0178) (9.2373, -22.0504) (9.2717, -22.0763) (9.2976, -22.0957) (9.3149, -22.1085) (9.3235, -22.115) knots 0 0 0 0 0 0 0.01428571 0.02857143 0.04285714 0.05714286 0.07142857 0.08571429 0.1 0.11428571 0.12857143 0.14285714 0.15714286 0.17142857 0.18571429 0.2 0.21428571 0.22857143 0.24285714 0.25714286 0.27142857 0.28571429 0.3 0.31428571 0.32857143 0.34285714 0.35714286 0.37142857 0.38571429 0.4 0.41428571 0.42857143 0.44285714 0.45714286 0.47142857 0.48571429 0.5 0.51428571 0.52857143 0.54285714 0.55714286 0.57142857 0.58571429 0.6 0.61428571 0.62857143 0.64285714 0.65714286 0.67142857 0.68571429 0.7 0.71428571 0.72857143 0.74285714 0.75714286 0.77142857 0.78571429 0.8 0.81428571 0.82857143 0.84285714 0.85714286 0.87142857 0.88571429 0.9 0.91428571 0.92857143 0.94285714 0.95714286 0.97142857 0.98571429 1 1 1 1 1 1
  arc A30 (9.3235, -22.115) -> (10.6078, -21.5285) centre (0, 0) ccw
  spline S15 degree 5 poles (10.6078, -21.5285) (10.6086, -21.5177) (10.6102, -21.4962) (10.6125, -21.464) (10.6154, -21.421) (10.6189, -21.3673) (10.622, -21.3138) (10.625, -21.2602) (10.6277, -21.2068) (10.6301, -21.1533) (10.6323, -21.1) (10.6342, -21.0467) (10.6359, -20.9935) (10.6373, -20.9403) (10.6385, -20.8872) (10.6394, -20.8342) (10.6401, -20.7812) (10.6405, -20.7283) (10.6406, -20.6755) (10.6405, -20.6228) (10.6401, -20.5701) (10.6395, -20.5175) (10.6386, -20.465) (10.6374, -20.4125) (10.636, -20.3602) (10.6342, -20.3079) (10.6322, -20.2557) (10.63, -20.2036) (10.6274, -20.1516) (10.6246, -20.0996) (10.6215, -20.0478) (10.6181, -19.996) (10.6144, -19.9444) (10.6105, -19.8928) (10.6062, -19.8414) (10.6017, -19.79) (10.5968, -19.7387) (10.5917, -19.6876) (10.5863, -19.6365) (10.5805, -19.5856) (10.5745, -19.5348) (10.5681, -19.4841) (10.5614, -19.4335) (10.5544, -19.383) (10.5471, -19.3326) (10.5395, -19.2824) (10.5315, -19.2323) (10.5232, -19.1823) (10.5146, -19.1325) (10.5056, -19.0828) (10.4963, -19.0332) (10.4866, -18.9838) (10.4765, -18.9346) (10.466, -18.8855) (10.4552, -18.8366) (10.4439, -18.7879) (10.4324, -18.7393) (10.4204, -18.6908) (10.4082, -18.6425) (10.3955, -18.5944) (10.3823, -18.5465) (10.3685, -18.4989) (10.3541, -18.4516) (10.3391, -18.4046) (10.3235, -18.3578) (10.3076, -18.3112) (10.2913, -18.2648) (10.2748, -18.2185) (10.2579, -18.1724) (10.2401, -18.1268) (10.2212, -18.0817) (10.2046, -18.0464) (10.1912, -18.0204) (10.1818, -18.0033) (10.1769, -17.9948) knots -1 -1 -1 -1 -1 -1 -0.98571429 -0.97142857 -0.95714286 -0.94285714 -0.92857143 -0.91428571 -0.9 -0.88571429 -0.87142857 -0.85714286 -0.84285714 -0.82857143 -0.81428571 -0.8 -0.78571429 -0.77142857 -0.75714286 -0.74285714 -0.72857143 -0.71428571 -0.7 -0.68571429 -0.67142857 -0.65714286 -0.64285714 -0.62857143 -0.61428571 -0.6 -0.58571429 -0.57142857 -0.55714286 -0.54285714 -0.52857143 -0.51428571 -0.5 -0.48571429 -0.47142857 -0.45714286 -0.44285714 -0.42857143 -0.41428571 -0.4 -0.38571429 -0.37142857 -0.35714286 -0.34285714 -0.32857143 -0.31428571 -0.3 -0.28571429 -0.27142857 -0.25714286 -0.24285714 -0.22857143 -0.21428571 -0.2 -0.18571429 -0.17142857 -0.15714286 -0.14285714 -0.12857143 -0.11428571 -0.1 -0.08571429 -0.07142857 -0.05714286 -0.04285714 -0.02857143 -0.01428571 0 0 0 0 0 0
  line L15 (10.1769, -17.9948) -> (10.1713, -17.9848)
  arc A31 (10.508, -16.6469) -> (10.1713, -17.9848) centre (11.0418, -17.4926) ccw
  arc A32 (10.508, -16.6469) -> (10.7774, -16.4738) centre (0, 0) ccw
  arc A33 (12.1343, -16.7233) -> (10.7774, -16.4738) centre (11.3249, -17.3106) ccw
  line L16 (12.1343, -16.7233) -> (12.141, -16.7326)
  spline S16 degree 5 poles (12.141, -16.7326) (12.1467, -16.7405) (12.1584, -16.7561) (12.1765, -16.7791) (12.2017, -16.8089) (12.2348, -16.8449) (12.2689, -16.88) (12.3038, -16.9145) (12.339, -16.9488) (12.3745, -16.9828) (12.4103, -17.0167) (12.4464, -17.0503) (12.4829, -17.0835) (12.52, -17.1162) (12.5576, -17.1485) (12.5956, -17.1804) (12.6341, -17.212) (12.6729, -17.2432) (12.7121, -17.2742) (12.7515, -17.3049) (12.7912, -17.3354) (12.8311, -17.3656) (12.8714, -17.3955) (12.912, -17.4251) (12.9529, -17.4545) (12.9941, -17.4835) (13.0356, -17.5123) (13.0774, -17.5409) (13.1194, -17.5692) (13.1617, -17.5972) (13.2042, -17.6251) (13.2469, -17.6526) (13.2899, -17.68) (13.3332, -17.7071) (13.3767, -17.7339) (13.4204, -17.7605) (13.4643, -17.7869) (13.5085, -17.8131) (13.5529, -17.839) (13.5975, -17.8647) (13.6424, -17.8901) (13.6874, -17.9154) (13.7327, -17.9404) (13.7781, -17.9652) (13.8238, -17.9898) (13.8697, -18.0142) (13.9157, -18.0383) (13.962, -18.0622) (14.0084, -18.0859) (14.0551, -18.1094) (14.1019, -18.1327) (14.149, -18.1558) (14.1962, -18.1787) (14.2436, -18.2013) (14.2911, -18.2237) (14.3389, -18.246) (14.3868, -18.268) (14.4349, -18.2898) (14.4832, -18.3114) (14.5316, -18.3328) (14.5803, -18.354) (14.6291, -18.375) (14.678, -18.3958) (14.7271, -18.4163) (14.7764, -18.4367) (14.8258, -18.4569) (14.8754, -18.4769) (14.9252, -18.4966) (14.9751, -18.5162) (15.0252, -18.5356) (15.0754, -18.5547) (15.1157, -18.5699) (15.146, -18.5812) (15.1662, -18.5887) (15.1764, -18.5924) knots 0 0 0 0 0 0 0.01428571 0.02857143 0.04285714 0.05714286 0.07142857 0.08571429 0.1 0.11428571 0.12857143 0.14285714 0.15714286 0.17142857 0.18571429 0.2 0.21428571 0.22857143 0.24285714 0.25714286 0.27142857 0.28571429 0.3 0.31428571 0.32857143 0.34285714 0.35714286 0.37142857 0.38571429 0.4 0.41428571 0.42857143 0.44285714 0.45714286 0.47142857 0.48571429 0.5 0.51428571 0.52857143 0.54285714 0.55714286 0.57142857 0.58571429 0.6 0.61428571 0.62857143 0.64285714 0.65714286 0.67142857 0.68571429 0.7 0.71428571 0.72857143 0.74285714 0.75714286 0.77142857 0.78571429 0.8 0.81428571 0.82857143 0.84285714 0.85714286 0.87142857 0.88571429 0.9 0.91428571 0.92857143 0.94285714 0.95714286 0.97142857 0.98571429 1 1 1 1 1 1
  arc A34 (15.1764, -18.5924) -> (16.2434, -17.6679) centre (0, 0) ccw
  spline S17 degree 5 poles (16.2434, -17.6679) (16.2411, -17.6573) (16.2366, -17.6362) (16.2297, -17.6046) (16.2204, -17.5626) (16.2086, -17.5101) (16.1966, -17.4578) (16.1843, -17.4056) (16.1718, -17.3536) (16.1591, -17.3016) (16.1462, -17.2498) (16.133, -17.1981) (16.1196, -17.1466) (16.106, -17.0952) (16.0922, -17.0439) (16.0781, -16.9928) (16.0638, -16.9418) (16.0493, -16.8909) (16.0346, -16.8402) (16.0196, -16.7896) (16.0044, -16.7392) (15.989, -16.6889) (15.9733, -16.6388) (15.9574, -16.5888) (15.9412, -16.5389) (15.9249, -16.4893) (15.9082, -16.4398) (15.8914, -16.3904) (15.8743, -16.3412) (15.8569, -16.2922) (15.8394, -16.2433) (15.8215, -16.1946) (15.8034, -16.1461) (15.7851, -16.0977) (15.7665, -16.0495) (15.7477, -16.0015) (15.7286, -15.9537) (15.7093, -15.9061) (15.6897, -15.8586) (15.6698, -15.8114) (15.6497, -15.7643) (15.6293, -15.7174) (15.6087, -15.6708) (15.5877, -15.6243) (15.5665, -15.5781) (15.545, -15.532) (15.5233, -15.4862) (15.5012, -15.4406) (15.4789, -15.3952) (15.4563, -15.35) (15.4334, -15.3051) (15.4102, -15.2604) (15.3866, -15.216) (15.3628, -15.1719) (15.3385, -15.128) (15.314, -15.0844) (15.2892, -15.041) (15.2641, -14.9979) (15.2388, -14.955) (15.213, -14.9125) (15.1869, -14.8702) (15.1602, -14.8284) (15.1331, -14.7871) (15.1054, -14.7462) (15.0773, -14.7057) (15.0489, -14.6655) (15.0202, -14.6255) (14.9914, -14.5858) (14.9621, -14.5463) (14.9322, -14.5075) (14.9013, -14.4697) (14.8755, -14.4405) (14.8553, -14.4193) (14.8414, -14.4055) (14.8344, -14.3987) knots -1 -1 -1 -1 -1 -1 -0.98571429 -0.97142857 -0.95714286 -0.94285714 -0.92857143 -0.91428571 -0.9 -0.88571429 -0.87142857 -0.85714286 -0.84285714 -0.82857143 -0.81428571 -0.8 -0.78571429 -0.77142857 -0.75714286 -0.74285714 -0.72857143 -0.71428571 -0.7 -0.68571429 -0.67142857 -0.65714286 -0.64285714 -0.62857143 -0.61428571 -0.6 -0.58571429 -0.57142857 -0.55714286 -0.54285714 -0.52857143 -0.51428571 -0.5 -0.48571429 -0.47142857 -0.45714286 -0.44285714 -0.42857143 -0.41428571 -0.4 -0.38571429 -0.37142857 -0.35714286 -0.34285714 -0.32857143 -0.31428571 -0.3 -0.28571429 -0.27142857 -0.25714286 -0.24285714 -0.22857143 -0.21428571 -0.2 -0.18571429 -0.17142857 -0.15714286 -0.14285714 -0.12857143 -0.11428571 -0.1 -0.08571429 -0.07142857 -0.05714286 -0.04285714 -0.02857143 -0.01428571 0 0 0 0 0 0
  line L17 (14.8344, -14.3987) -> (14.8262, -14.3907)
  arc A35 (14.7723, -13.0122) -> (14.8262, -14.3907) centre (15.5227, -13.6732) ccw
  arc A36 (14.7723, -13.0122) -> (14.9821, -12.7701) centre (0, 0) ccw
  arc A37 (16.3543, -12.6273) -> (14.9821, -12.7701) centre (15.7431, -13.4188) ccw
  line L18 (16.3543, -12.6273) -> (16.3633, -12.6343)
  spline S18 degree 5 poles (16.3633, -12.6343) (16.371, -12.6403) (16.3866, -12.652) (16.4105, -12.669) (16.4431, -12.6904) (16.4849, -12.7156) (16.5276, -12.7397) (16.5708, -12.763) (16.6142, -12.7859) (16.6579, -12.8086) (16.7017, -12.831) (16.7458, -12.8531) (16.7902, -12.8746) (16.835, -12.8956) (16.8802, -12.916) (16.9257, -12.9359) (16.9715, -12.9553) (17.0176, -12.9744) (17.0638, -12.993) (17.1103, -13.0114) (17.157, -13.0295) (17.2038, -13.0472) (17.2509, -13.0646) (17.2982, -13.0815) (17.3457, -13.0982) (17.3934, -13.1145) (17.4414, -13.1304) (17.4895, -13.146) (17.5378, -13.1613) (17.5862, -13.1764) (17.6349, -13.1911) (17.6836, -13.2055) (17.7326, -13.2196) (17.7817, -13.2334) (17.831, -13.2469) (17.8805, -13.2601) (17.9301, -13.2731) (17.9798, -13.2857) (18.0298, -13.2981) (18.0798, -13.3102) (18.13, -13.322) (18.1803, -13.3335) (18.2308, -13.3448) (18.2814, -13.3558) (18.3321, -13.3665) (18.383, -13.3769) (18.434, -13.3871) (18.4851, -13.397) (18.5364, -13.4067) (18.5878, -13.4161) (18.6393, -13.4252) (18.6909, -13.4341) (18.7426, -13.4428) (18.7945, -13.4511) (18.8465, -13.4593) (18.8985, -13.4671) (18.9507, -13.4748) (19.003, -13.4821) (19.0554, -13.4893) (19.108, -13.4962) (19.1606, -13.5028) (19.2133, -13.5092) (19.2661, -13.5153) (19.3191, -13.5212) (19.3721, -13.5269) (19.4252, -13.5323) (19.4784, -13.5375) (19.5317, -13.5425) (19.5851, -13.5472) (19.6386, -13.5517) (19.6922, -13.5559) (19.7352, -13.5591) (19.7674, -13.5614) (19.7889, -13.5629) (19.7997, -13.5636) knots 0 0 0 0 0 0 0.01428571 0.02857143 0.04285714 0.05714286 0.07142857 0.08571429 0.1 0.11428571 0.12857143 0.14285714 0.15714286 0.17142857 0.18571429 0.2 0.21428571 0.22857143 0.24285714 0.25714286 0.27142857 0.28571429 0.3 0.31428571 0.32857143 0.34285714 0.35714286 0.37142857 0.38571429 0.4 0.41428571 0.42857143 0.44285714 0.45714286 0.47142857 0.48571429 0.5 0.51428571 0.52857143 0.54285714 0.55714286 0.57142857 0.58571429 0.6 0.61428571 0.62857143 0.64285714 0.65714286 0.67142857 0.68571429 0.7 0.71428571 0.72857143 0.74285714 0.75714286 0.77142857 0.78571429 0.8 0.81428571 0.82857143 0.84285714 0.85714286 0.87142857 0.88571429 0.9 0.91428571 0.92857143 0.94285714 0.95714286 0.97142857 0.98571429 1 1 1 1 1 1
  arc A38 (19.7997, -13.5636) -> (20.563, -12.3759) centre (0, 0) ccw
  spline S19 degree 5 poles (20.563, -12.3759) (20.5579, -12.3664) (20.5476, -12.3475) (20.5321, -12.3191) (20.5113, -12.2814) (20.4852, -12.2344) (20.4589, -12.1876) (20.4324, -12.1409) (20.4058, -12.0945) (20.379, -12.0483) (20.352, -12.0022) (20.3248, -11.9563) (20.2974, -11.9106) (20.2699, -11.8651) (20.2422, -11.8198) (20.2143, -11.7747) (20.1862, -11.7298) (20.1579, -11.6851) (20.1295, -11.6406) (20.1009, -11.5963) (20.0721, -11.5522) (20.0431, -11.5083) (20.0139, -11.4646) (19.9846, -11.4211) (19.9551, -11.3778) (19.9254, -11.3348) (19.8955, -11.292) (19.8654, -11.2494) (19.8351, -11.207) (19.8047, -11.1648) (19.774, -11.1229) (19.7432, -11.0812) (19.7122, -11.0397) (19.681, -10.9985) (19.6496, -10.9575) (19.618, -10.9167) (19.5862, -10.8762) (19.5542, -10.836) (19.522, -10.7959) (19.4897, -10.7562) (19.4571, -10.7167) (19.4243, -10.6775) (19.3914, -10.6385) (19.3582, -10.5999) (19.3248, -10.5615) (19.2912, -10.5233) (19.2574, -10.4855) (19.2234, -10.4479) (19.1892, -10.4107) (19.1548, -10.3737) (19.1202, -10.337) (19.0853, -10.3007) (19.0502, -10.2648) (19.0149, -10.2291) (18.9793, -10.1939) (18.9435, -10.1589) (18.9075, -10.1243) (18.8712, -10.09) (18.8348, -10.056) (18.7981, -10.0224) (18.7611, -9.9893) (18.7238, -9.9567) (18.6861, -9.9246) (18.648, -9.8932) (18.6097, -9.8622) (18.5711, -9.8317) (18.5323, -9.8014) (18.4934, -9.7714) (18.4542, -9.7418) (18.4146, -9.713) (18.3743, -9.6853) (18.3413, -9.6646) (18.3159, -9.65) (18.2988, -9.6407) (18.2901, -9.6361) knots -1 -1 -1 -1 -1 -1 -0.98571429 -0.97142857 -0.95714286 -0.94285714 -0.92857143 -0.91428571 -0.9 -0.88571429 -0.87142857 -0.85714286 -0.84285714 -0.82857143 -0.81428571 -0.8 -0.78571429 -0.77142857 -0.75714286 -0.74285714 -0.72857143 -0.71428571 -0.7 -0.68571429 -0.67142857 -0.65714286 -0.64285714 -0.62857143 -0.61428571 -0.6 -0.58571429 -0.57142857 -0.55714286 -0.54285714 -0.52857143 -0.51428571 -0.5 -0.48571429 -0.47142857 -0.45714286 -0.44285714 -0.42857143 -0.41428571 -0.4 -0.38571429 -0.37142857 -0.35714286 -0.34285714 -0.32857143 -0.31428571 -0.3 -0.28571429 -0.27142857 -0.25714286 -0.24285714 -0.22857143 -0.21428571 -0.2 -0.18571429 -0.17142857 -0.15714286 -0.14285714 -0.12857143 -0.11428571 -0.1 -0.08571429 -0.07142857 -0.05714286 -0.04285714 -0.02857143 -0.01428571 0 0 0 0 0 0
  line L19 (18.2901, -9.6361) -> (18.28, -9.6308)
  arc A39 (17.8399, -8.3233) -> (18.28, -9.6308) centre (18.7461, -8.7461) ccw
  arc A40 (17.8399, -8.3233) -> (17.9729, -8.0319) centre (0, 0) ccw
  arc A41 (19.2493, -7.5083) -> (17.9729, -8.0319) centre (18.8859, -8.4399) ccw
  line L20 (19.2493, -7.5083) -> (19.26, -7.5124)